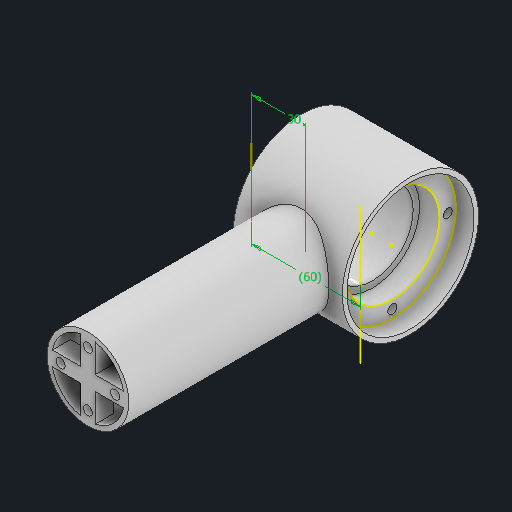
# Autodesk Inventor part: 22.10.2025-16-t
Saved by Autodesk Inventor 2026.1 (Build 301233020, 233B)
## iProperties
Created: 2026-01-11
Part Number: 22.10.2025-16-t
Material: Ogólny
Document SubType Name: Modeling
Designer: Nitro
Density: 1 g/cm^3
Appearance: Domyślna
Author: Nitro
Autodesk Inventor part; units mm, degrees
ref_plane "YZ Plane" through (0, 0, 0) normal (1, 0, 0) x (0, 1, 0)
ref_plane "XZ Plane" through (0, 0, 0) normal (0, 1, 0) x (-1, 0, 0)
sketch "Szkic1" plane through (0, 0, 0) normal (1, 0, 0) x (0, 1, 0)
  circle A0 centre (0, 0) radius 26
  circle A1 centre (0, 0) radius 35
  circle A2 centre (0, 0) radius 37.5
  dimension "d0" = 52
  dimension "d1" = 70
  dimension "d2" = 75
  constraints: 3 centre point, 3 coincident
  measures "d0" diameter of A0
  measures "d1" diameter of A1
  measures "d2" diameter of A2
extrude "Wyciągnięcie proste1" add sketch "Szkic1" along normal blind 60 contours A0 | A1 | A2
sketch "Szkic2" plane through (60, 0, 0) normal (1, 0, 0) x (0, 0, -1)
  circle A0 centre (0, 0) radius 35
  dimension "d5" = 70
  constraints: 1 centre point, 1 coincident
  measures "d5" diameter of A0
extrude "Wyciągnięcie proste2" cut sketch "Szkic2" against normal blind 10
sketch "Szkic3" plane through (50, 0, 0) normal (1, 0, 0) x (0, 0, -1)
  circle A0 centre (0, 0) radius 26
  dimension "d8" = 52
  constraints: 1 centre point, 1 coincident
  measures "d8" diameter of A0
extrude "Wyciągnięcie proste3" cut sketch "Szkic3" against normal blind 11
sketch "Szkic4" plane through (0, 0, 0) normal (-1, 0, 0) x (0, 0, 1)
  circle A0 centre (0, 0) radius 26
  dimension "d11" = 52
  constraints: 1 centre point, 1 coincident
  measures "d11" diameter of A0
extrude "Wyciągnięcie proste4" cut sketch "Szkic4" against normal blind 7
sketch "Szkic5" plane through (39, 0, 0) normal (1, 0, 0) x (0, 0, -1)
  point P0 (0, 0)
sketch "Szkic6" plane through (39, 0, 0) normal (1, 0, 0) x (0, 0, -1)
  circle A0 centre (0, 0) radius 22.5
  dimension "d14" = 45
  constraints: 1 centre point, 1 coincident
  measures "d14" diameter of A0
extrude "Wyciągnięcie proste5" cut sketch "Szkic6" against normal blind 70
ref_plane "Płaszczyzna konstrukcyjna1" through (0, 0, 27.5) normal (0, 0, 1) x (1, 0, 0)
sketch "Szkic7" plane through (0, 0, 27.5) normal (0, 0, 1) x (1, 0, 0)
  line L0 (60, -37.5) -> (60, 37.5) projected
  line L1 (0, -37.5) -> (0, 37.5) projected
  line L2 (60, 0) -> (0, 0)
  point P0 (30, 0)
  dimension "d18" = 60
  dimension "d19" = 30
  constraints: 3 midpoint, 2 end point, 1 perpendicular
  measures "d18" distance of L2.end L2.start
  measures "d19" distance of point (0, 0) point (30, 0)
sketch "Szkic8" plane through (0, 0, 27.5) normal (0, 0, 1) x (1, 0, 0)
  line L0 (60, -37.5) -> (60, 37.5) projected
  line L1 (0, -37.5) -> (0, 37.5) projected
  line L2 (39, 22.5) -> (7, 22.5) projected
  line L3 (0, -37.5) -> (0, 37.5) projected
  circle A0 centre (30, 0) radius 22.5
  point P0 (0, 0)
  point P1 (0, 0)
  dimension "d20" = 30
  dimension "d21" = 45
  constraints: 1 centre point, 1 coincident, 1 midpoint
  measures "d20" distance of point (0, 0) point (30, 0)
  measures "d21" diameter of A0
extrude "Wyciągnięcie proste6" add sketch "Szkic8" along normal blind 70
sketch "Szkic9" plane through (30, 0, 97.5) normal (0, 0, 1) x (1, 0, 0)
  point P0 (-30, 0)
sketch "Szkic10" plane through (30, 0, 97.5) normal (0, 0, 1) x (1, 0, 0)
  line L0 (9, 26) -> (9, -26) projected
  circle A0 centre (0, 0) radius 22.5 projected
  point P0 (-30, 0)
extrude "Wyciągnięcie proste7" add sketch "Szkic10" along normal blind 50
sketch "Szkic11" plane through (50, 0, 0) normal (1, 0, 0) x (0, 0, -1)
  point P0 (0, 0)
sketch "Szkic12" plane through (50, 0, 0) normal (1, 0, 0) x (0, 0, -1)
  line L0 (-33.4477, 10.3078) -> (-27.5, 10.3078) projected
  line L1 (-27.5, 10.3078) -> (-27.5, -10.3078) projected
  line L2 (-27.5, -10.3078) -> (-33.4477, -10.3078) projected
  arc A0 (-33.4477, -10.3078) -> (-33.4477, 10.3078) centre (0, 0) ccw projected
  circle A1 centre (0, 0) radius 26 projected
sketch "Szkic13" plane through (50, 0, 0) normal (1, 0, 0) x (0, 0, -1)
  circle A0 centre (0, 0) radius 35
  dimension "d26" = 70
  constraints: 1 centre point, 1 coincident
  measures "d26" diameter of A0
extrude "Wyciągnięcie proste8" cut sketch "Szkic13" along normal blind 50
sketch "Szkic14" plane through (50, 0, 0) normal (1, 0, 0) x (0, 0, -1)
  circle A0 centre (0, 0) radius 30.5
  point P0 (-30.5, 0)
  point P1 (0, -30.5)
  point P2 (30.5, 0)
  point P3 (0, 30.5)
  dimension "d29" = 61
  dimension "d32" = 360
  constraints: 1 coincident, 1 horizontal alignment, 7 other
hole "Otwór1" at (50, 0, 30.5) at (50, -30.5, 0) at (50, 0, -30.5) at (50, 30.5, 0) direction (-1, 0, 0) diameter 5 depth 30
thread "Gwint1" size "M5x0.8" class "6H" standard "ANSI Metric M Profile" full length
thread "Gwint2" size "M5x0.8" class "6H" standard "ANSI Metric M Profile" full length
thread "Gwint3" size "M5x0.8" class "6H" standard "ANSI Metric M Profile" full length
thread "Gwint4" size "M5x0.8" class "6H" standard "ANSI Metric M Profile" full length
sketch "Szkic15" plane through (30, 0, 147.5) normal (0, 0, 1) x (1, 0, 0)
  circle A0 centre (0, 0) radius 22.5 projected
  circle A1 centre (0, 0) radius 20
  point P0 (-30, 0)
  dimension "d49" = 40
  constraints: 1 centre point, 1 coincident
  measures "d49" diameter of A1
extrude "Wyciągnięcie proste9" cut sketch "Szkic15" against normal blind 113 contours A1
sketch "Szkic16" plane through (30, 0, 147.5) normal (0, 0, 1) x (1, 0, 0)
  circle A0 centre (0, 0) radius 20 projected
  circle A1 centre (0, 0) radius 22.5 projected
  line L0 (0, 20) -> (0, -20)
  line L1 (0, -20) -> (4, -20)
  line L2 (4, -20) -> (4, 20)
  line L3 (4, 20) -> (0, 20)
  line L4 (0, 20) -> (0, -20)
  line L5 (0, -20) -> (-4, -20)
  line L6 (-4, -20) -> (-4, 20)
  line L7 (-4, 20) -> (0, 20)
  line L8 (20, 0) -> (-20, 0)
  line L9 (-20, 0) -> (-20, 4)
  line L10 (-20, 4) -> (20, 4)
  line L11 (20, 4) -> (20, 0)
  line L12 (-20, 0) -> (20, 0)
  line L13 (20, 0) -> (20, -4)
  line L14 (20, -4) -> (-20, -4)
  line L15 (-20, -4) -> (-20, 0)
  point P0 (-30, 0)
  point P1 (-4, 19.5959)
  point P2 (-4, 4)
  point P3 (-19.5959, 4)
  point P4 (-19.5959, -4)
  point P5 (-4, -4)
  point P6 (-4, -19.5959)
  point P7 (4, -19.5959)
  point P8 (4, -4)
  point P9 (19.5959, -4)
  point P10 (19.5959, 4)
  point P11 (4, 4)
  point P12 (4, 19.5959)
  dimension "d52" = 4
  dimension "d53" = 4
  dimension "d54" = 4
  dimension "d55" = 4
  constraints: 32 end point, 9 parallel, 6 perpendicular, 4 point on circle, 1 vertical
  measures "d52" distance of L1.end L0.end
  measures "d53" distance of L0.end L5.end
  measures "d54" distance of L8.end L9.end
  measures "d55" distance of L8.start L13.end
extrude "Wyciągnięcie proste10" add sketch "Szkic16" against normal blind 10 contours L8 L2 L10 A0 | A0 L14 L2 L8 | L8 L0 L10 L2 | L2 L14 L0 L8 | L2 L10 L0 A0 | A0 L0 L14 L2 | L8 L6 L10 L0 | L0 L14 L6 L8 | L0 L10 L6 A0 | A0 L6 L14 L0 | L8 A0 L10 L6 | L6 L14 A0 L8
sketch "Szkic17" plane through (30, 0, 147.5) normal (0, 0, 1) x (1, 0, 0)
  circle A0 centre (0, 0) radius 15
  circle A1 centre (0, 0) radius 22.5 projected
  point P0 (-30, 0)
  point P1 (15, 0)
  point P2 (0, -15)
  point P3 (-15, 0)
  point P4 (0, 15)
  dimension "d58" = 30
  dimension "d59" = 7.5
  constraints: 4 point on circle, 1 centre point
  measures "d58" diameter of A0
  measures "d59" radial gap between concentric circles of A1 A0
hole "Otwór2" at (45, 0, 147.5) at (30, -15, 147.5) at (15, 0, 147.5) at (30, 15, 147.5) direction (0, 0, -1) diameter 5 depth 30
thread "Gwint5" size "M5x0.8" class "6H" standard "ANSI Metric M Profile" full length
thread "Gwint6" size "M5x0.8" class "6H" standard "ANSI Metric M Profile" full length
thread "Gwint7" size "M5x0.8" class "6H" standard "ANSI Metric M Profile" full length
thread "Gwint8" size "M5x0.8" class "6H" standard "ANSI Metric M Profile" full length
equation "\"d82\" = 55deg"
equation "\"Szkic18_Pitch\" = 0.8"
equation "\"d100\" = 55deg"
equation "\"Szkic20_Pitch\" = 0.8"
equation "\"d118\" = 55deg"
equation "\"Szkic22_Pitch\" = 0.8"
equation "\"d136\" = 55deg"
equation "\"Szkic24_Pitch\" = 0.8"
equation "\"d154\" = 55deg"
equation "\"Szkic26_Pitch\" = 0.8"
equation "\"d172\" = 55deg"
equation "\"Szkic28_Pitch\" = 0.8"
equation "\"d190\" = 55deg"
equation "\"Szkic30_Pitch\" = 0.8"
equation "\"d208\" = 55deg"
equation "\"Szkic32_Pitch\" = 0.8"
